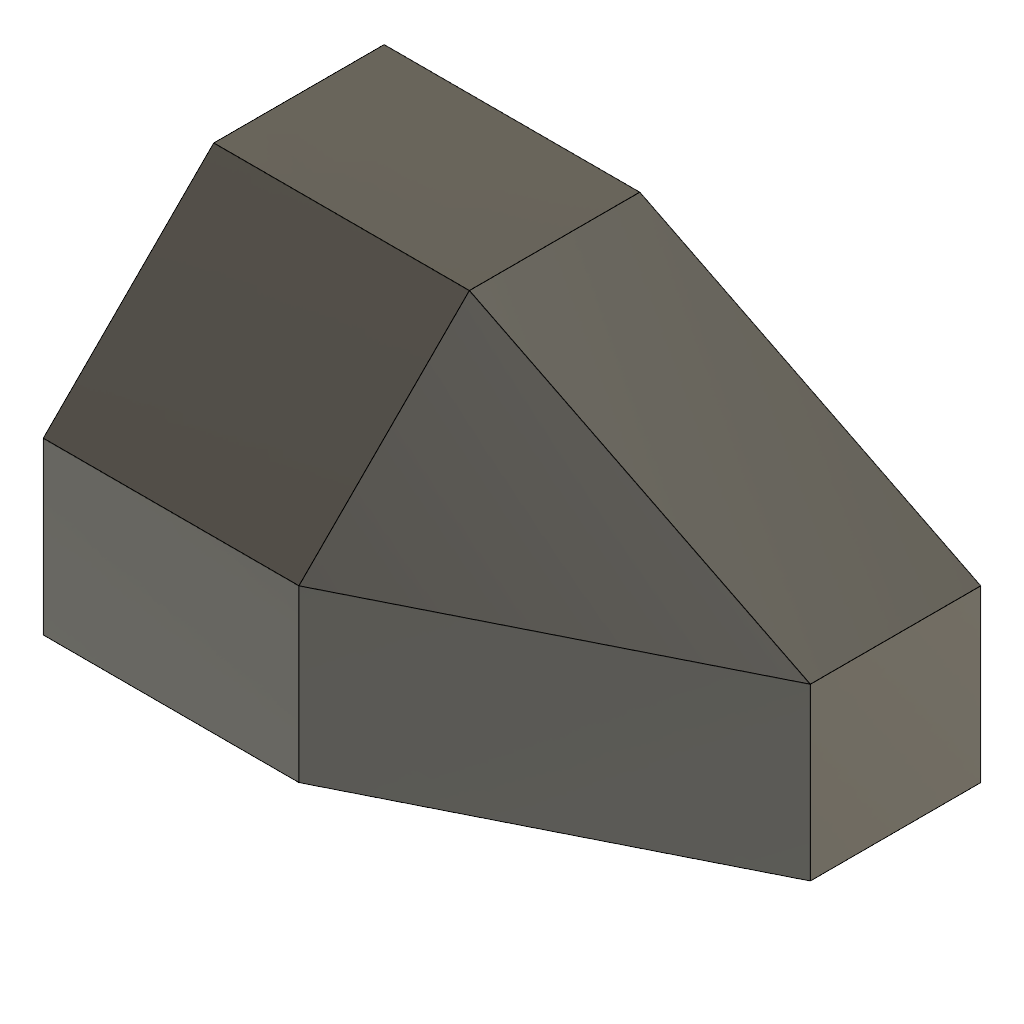
Weird Loft (Autodesk Fusion 360 design; units mm, degrees)
part number: 2026-11-08-00-24-16-475
Autodesk Fusion 360 part; units mm, degrees
sketch "Sketch1" plane through (0, 0, 0) normal (0, 1, 0) x (1, 0, 0)
  line L0 (15, 10) -> (-15, 10)
  line L1 (-15, 10) -> (-15, -10)
  line L2 (-15, -10) -> (15, -10)
  line L3 (15, -10) -> (15, 10)
  line L4 (15, 10) -> (-15, -10) construction
  line L5 (-15, 10) -> (15, -10) construction
  dimension "d1" = 30
  dimension "d2" = 20
  constraint horizontal L0
  constraint perpendicular L0 L1
  constraint parallel L0 L2
  constraint parallel L1 L3
  constraint coincident L4 origin
  constraint coincident L5 origin
  measures "d1" distance of L1.end L2.end
  measures "d2" distance of L0.end L1.end
extrude "Extrude1" add sketch "Sketch1" along normal blind 40
sketch "Sketch2" plane through (15, 0, 0) normal (1, 0, 0) x (0, 1, 0)
  line L0 (0, 10) -> (0, -10)
  line L1 (0, -10) -> (40, -10)
  line L2 (40, -10) -> (40, 10)
  line L3 (40, 10) -> (0, 10)
  line L4 (40, 10) -> (20, 10)
  line L5 (20, 10) -> (20, 30)
  line L6 (20, 30) -> (40, 30)
  line L7 (40, 30) -> (40, 10)
  dimension "d5" = 20
  constraint horizontal L4
  constraint vertical L5
  constraint horizontal L6
  constraint vertical L7
  constraint coincident L2.end L3.start
  measures "d5" distance of L2.end L6.end
extrude "Extrude2" add sketch "Sketch2" against normal blind 30 contours L3 L4 L5 L6 L7
sketch "Sketch3" plane through (15, 0, 0) normal (1, 0, 0) x (0, 1, 0)
  line L0 (0, 10) -> (0, -10)
  line L1 (0, -10) -> (40, -10)
  line L2 (40, -10) -> (40, 30)
  line L3 (40, 30) -> (20, 30)
  line L4 (20, 30) -> (20, 10)
  line L5 (20, 10) -> (0, 10)
  line L6 (0, 10) -> (20, 30)
  line L7 (20, 10) -> (40, 10)
  line L8 (40, 10) -> (40, -10)
  line L9 (40, -10) -> (20, -10)
  line L10 (20, -10) -> (20, 10)
  constraint coincident L0.start L5.end
  constraint coincident L3.end L4.start
  constraint horizontal L7
  constraint vertical L8
  constraint horizontal L9
  constraint vertical L10
  constraint coincident L1.end L2.start
  constraint coincident L4.end L5.start
extrude "Extrude3" add sketch "Sketch3" against normal blind 30 contours L4 L5 L6
extrude "Extrude4" add sketch "Sketch3" along normal blind 40 contours L1 L2 L7 L8 L9 L10
sketch "Sketch4" plane through (0, 0, 10) normal (0, 0, 1) x (-1, 0, 0)
  line L0 (-15, -40) -> (-15, -20)
  line L1 (-15, -20) -> (-55, -20)
  line L2 (-55, -20) -> (-55, -40)
  line L3 (-55, -40) -> (-15, -40)
  line L4 (-55, -20) -> (-15, 0)
  line L5 (-15, 0) -> (-15, -20)
  point P0 (-15, 0)
  constraint coincident L1.end L2.start
  constraint coincident P0 L4.end
  constraint coincident L0.end L1.start
extrude "Extrude5" add sketch "Sketch4" against normal blind 20 contours L1 L4 L5
sketch "Sketch5" plane through (0, 40, 0) normal (0, 1, 0) x (-1, 0, 0)
  line L0 (-15, 30) -> (-15, 10)
  line L1 (-15, 10) -> (-55, 10)
  line L2 (-55, 10) -> (-55, -10)
  line L3 (-55, -10) -> (15, -10)
  line L4 (15, -10) -> (15, 30)
  line L5 (15, 30) -> (-15, 30)
  line L6 (-55, 10) -> (-15, 30)
  constraint coincident L1.end L2.start
  constraint coincident L0.start L5.end
extrude "Extrude6" add sketch "Sketch5" against normal blind 20 contours L0 L1 L6
loft "Loft1" add profiles "Sketch3" section 1 contours L4 L5 L6 section 2 point at (55, 20, 10)
